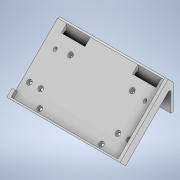
# Autodesk Inventor part: uMogi2_Tarto
Saved by Autodesk Inventor 2021 (Build 250183000, 183)
## iProperties
Created: 2021-04-12
Part Number: uMogi2_Tarto
Material: Generic
Document SubType Name: Modeling
Designer: Honti
Density: 1 g/cm^3
Appearance: Default
Author: Honti
Autodesk Inventor part; units mm, degrees
ref_plane "YZ Plane" through (0, 0, 0) normal (1, 0, 0) x (0, 1, 0)
ref_plane "XZ Plane" through (0, 0, 0) normal (0, 1, 0) x (-1, 0, 0)
ref_plane "XY Plane" through (0, 0, 0) normal (0, 0, 1) x (1, 0, 0)
sketch "Sketch1" plane through (0, 0, 0) normal (1, 0, 0) x (0, 1, 0)
  line L0 (0, 0) -> (33, 0)
  line L1 (-27.1041, 63.1041) -> (-29.2254, 60.9828)
  line L2 (28.7574, 3) -> (0, 3)
  line L3 (0, 3) -> (0, 0)
  line L4 (33, 0) -> (33, 3)
  line L5 (33, 3) -> (-27.1041, 63.1041)
  line L6 (28.7574, 3) -> (28.7574, 3)
  line L7 (28.7574, 3) -> (-29.2254, 60.9828)
  line L8 (15, 3) -> (15, 16.7574)
  dimension "d0" = 3
  dimension "d51" = 33
  dimension "d52" = 3
  dimension "d53" = 45
  dimension "d55" = 0
  dimension "d82" = 85
  dimension "d104" = 15
  constraints: 18 end point, 3 point on line, 3 vertical, 2 parallel, 2 perpendicular, 1 horizontal
  measures "d0" distance between parallel lines of L2 L0
  measures "d51" distance of L0.start L0.end
  measures "d52" distance between parallel lines of L5 L7
  measures "d53" angle of L2 L7
  measures "d55" distance of L2.start L6.end
  measures "d82" distance from line of L4.end L1
  measures "d104" distance between parallel lines of L3 L8
extrude "Extrusion1" add sketch "Sketch1" along normal mid plane 145 contours L3 L2 L7 L1 L5 L4 L0
sketch "Sketch2" plane through (-72.5, -23.5685, 59.5685) normal (0, 0.7071, 0.7071) x (1, 0, 0)
  line L0 (0, -5) -> (145, -5)
  line L1 (145, -5) -> (145, -3)
  line L2 (145, -3) -> (0, -3)
  line L3 (0, -3) -> (0, -5)
  line L4 (0, -3) -> (145, -3)
  line L5 (145, -3) -> (145, -1)
  line L6 (145, -1) -> (0, -1)
  line L7 (0, -1) -> (0, -3)
  line L8 (0, -5) -> (145, -5) projected
  line L9 (145, 82.1213) -> (143, 82.1213)
  line L10 (143, 82.1213) -> (143, -5)
  line L11 (143, -5) -> (145, -5)
  line L12 (145, -5) -> (145, 82.1213)
  line L13 (0, -5) -> (2, -5)
  line L14 (2, -5) -> (2, 4.5)
  line L15 (2, 4.5) -> (0, 4.5)
  line L16 (0, 4.5) -> (0, -5)
  line L17 (2, 4.5) -> (4, 4.5)
  line L18 (4, 4.5) -> (4, -5)
  line L19 (4, -5) -> (2, -5)
  line L20 (2, -5) -> (2, 4.5)
  line L21 (143, 82.1213) -> (141, 82.1213)
  line L22 (141, 82.1213) -> (141, -5)
  line L23 (141, -5) -> (143, -5)
  line L24 (143, -5) -> (143, 82.1213)
  line L25 (145, 80) -> (145, -5) projected
  line L26 (0, 80) -> (145, 80) projected
  line L27 (0, 82.1213) -> (145, 82.1213) projected
  point P0 (72.5, 58.7868)
  point P1 (2, -3)
  point P2 (143, -3)
  point P3 (141, -1)
  point P4 (4, -1)
  point P5 (141, -3)
  point P6 (4, -3)
  point P7 (145, -3)
  dimension "d7" = 2
  dimension "d8" = 2
  dimension "d9" = 2
  dimension "d10" = 2
  dimension "d11" = 2
  dimension "d12" = 2
  dimension "d20" = 7.5
  constraints: 48 end point, 12 parallel, 6 horizontal, 6 perpendicular, 5 collinear, 3 point on line
  measures "d7" distance of L2.end L0.start
  measures "d8" distance between parallel lines of L2 L6
  measures "d9" distance of L14.end L15.end
  measures "d10" distance of L9.start L9.end
  measures "d11" distance of L14.end L17.end
  measures "d12" distance of L9.end L21.end
  measures "d20" distance between parallel lines of L2 L17
extrude "Extrusion2" add sketch "Sketch2" along normal blind 7 contours L3 L2 L14 L0 | L14 L2 L18 L0 | L7 L6 L14 L2 | L18 L2 L22 L0 | L14 L6 L18 L2 | L16 L15 L14 L6 | L22 L2 L10 L0 | L14 L17 L18 L6 | L10 L2 L1 L0 | L22 L6 L10 L2 | L10 L6 L5 L2 | L22 L26 L10 L6 | L10 L26 L12 L6 | L22 L21 L10 L26 | L10 L9 L12 L26
extrude "Extrusion3" cut sketch "Sketch2" along normal blind 4 contours L14 L6 L18 L2 | L18 L6 L22 L2 | L14 L17 L18 L6 | L22 L6 L10 L2 | L22 L26 L10 L6 | L22 L21 L10 L26
chamfer "Chamfer1" distance 2 angle 45 2 edges at (-68.5, -20.2098, 61.8666) (68.5, 7.2335, 34.4234)
sketch "Sketch6" plane through (-72.5, 35.4142, 0.5858) normal (0, 0.7071, 0.7071) x (1, 0, 0)
  line L0 (33, -26.4142) -> (112, -26.4142) construction
  line L1 (112, -26.4142) -> (112, -82.4142) construction
  line L2 (112, -82.4142) -> (33, -82.4142) construction
  line L3 (33, -82.4142) -> (33, -26.4142) construction
  circle A0 centre (33, -26.4142) radius 1.75
  circle A1 centre (112, -26.4142) radius 1.75
  circle A2 centre (112, -82.4142) radius 1.75
  circle A3 centre (33, -82.4142) radius 1.75
  line L4 (0, -78.9142) -> (0, -3.4142) projected
  line L5 (2, -86.4142) -> (143, -86.4142) projected
  line L6 (72.5, -112.7506) -> (72.5, 22.6042) projected
  line L7 (-17.9809, -66.4142) -> (202.9102, -66.4142) construction
  circle A4 centre (8.5, -66.4142) radius 1.75
  circle A5 centre (23, -66.4142) radius 1.75
  circle A6 centre (122, -66.4142) radius 1.75
  circle A7 centre (136.5, -66.4142) radius 1.75
  line L8 (0, -6.4142) -> (145, -6.4142) projected
  circle A8 centre (33, -26.4142) radius 3
  circle A9 centre (112, -26.4142) radius 3
  circle A10 centre (8.5, -66.4142) radius 3
  circle A11 centre (23, -66.4142) radius 3
  circle A12 centre (122, -66.4142) radius 3
  circle A13 centre (136.5, -66.4142) radius 3
  circle A14 centre (33, -82.4142) radius 3
  circle A15 centre (112, -82.4142) radius 3
  line L9 (2, -66.4142) -> (28.3487, -66.4142)
  line L10 (28.3487, -66.4142) -> (28.3487, -37.4142)
  line L11 (28.3487, -37.4142) -> (2, -37.4142)
  line L12 (2, -37.4142) -> (2, -66.4142)
  point P0 (72.5, -24.6274)
  dimension "d39" = 3.5
  dimension "d40" = 3.5
  dimension "d41" = 3.5
  dimension "d42" = 3.5
  dimension "d43" = 56
  dimension "d44" = 79
  dimension "d58" = 4
  dimension "d59" = 3.5
  dimension "d60" = 3.5
  dimension "d61" = 3.5
  dimension "d62" = 3.5
  dimension "d63" = 14.5
  dimension "d64" = 14.5
  dimension "d67" = 60
  dimension "d69" = 10
  dimension "d70" = 10
  dimension "d71" = 6
  dimension "d73" = 6
  dimension "d74" = 6
  dimension "d75" = 6
  dimension "d76" = 6
  dimension "d77" = 6
  dimension "d78" = 6
  dimension "d79" = 6
  dimension "d105" = 29
  constraints: 18 end point, 16 centre point, 12 coincident, 5 point on line, 4 parallel, 3 horizontal, 2 perpendicular, 1 other
  measures "d39" diameter of A0
  measures "d40" diameter of A1
  measures "d41" diameter of A3
  measures "d42" diameter of A2
  measures "d43" distance of L2.end L0.start
  measures "d44" distance of L1.end L2.end
  measures "d58" distance between parallel lines of L2 L5
  measures "d59" diameter of A4
  measures "d60" diameter of A5
  measures "d61" diameter of A6
  measures "d62" diameter of A7
  measures "d63" distance of A5.centre A4.centre
  measures "d64" distance of A7.centre A6.centre
  measures "d67" distance between parallel lines of L8 L7
  measures "d69" distance from line of A5.centre L3
  measures "d70" distance from line of L1 A6.centre
  measures "d71" diameter of A8
  measures "d73" diameter of A9
  measures "d74" diameter of A12
  measures "d75" diameter of A13
  measures "d76" diameter of A11
  measures "d77" diameter of A10
  measures "d78" diameter of A15
  measures "d79" diameter of A14
  measures "d105" distance of L11.end L9.start
extrude "Extrusion6" cut sketch "Sketch6" against normal up to surface (3 mm away) contours A0 | A1 | A2 | A3 | L9 A4 | A4 L9 | L9 A5 | A5 L9 | A6 | A7
extrude "Extrusion7" cut sketch "Sketch6" against normal blind 2 contours L9 A10 A4 | A4 L9 A10 | L9 A5 A11 | A11 L9 A5 | A8 | A9 | A12 | A13 | A14 | A15
sketch "Sketch8" plane through (-72.5, 0, 0) normal (0, 1, 0) x (1, 0, 0)
  line L0 (103, -3) -> (133, -3)
  line L1 (133, -3) -> (133, -10)
  line L2 (133, -10) -> (103, -10)
  line L3 (103, -10) -> (103, -3)
  line L4 (0, -3) -> (145, -3) projected
  line L5 (133, -6.5) -> (103, -6.5)
  line L6 (143, -61.6899) -> (143, -3) projected
  line L7 (143, -61.6899) -> (143, -64.5183) projected
  line L8 (143, -64.5183) -> (143, -4.3284) projected
  line L9 (143, -1.5) -> (143, -4.3284) projected
  line L10 (143, -3) -> (143, -1.5) projected
  point P0 (72.5, 0)
  point P1 (136, -6.5)
  dimension "d88" = 7
  dimension "d89" = 30
  dimension "d111" = 10
  constraints: 10 end point, 3 parallel, 2 midpoint, 1 collinear, 1 horizontal, 1 perpendicular
  measures "d88" distance of L2.end L0.start
  measures "d89" distance of L1.end L2.end
  measures "d111" distance between parallel lines of L1 L8
extrude "Extrusion9" cut sketch "Sketch8" along normal blind 32 contours L5 L1 L2 L3
extrude "Extrusion10" cut sketch "Sketch8" along normal blind 35 contours L0 L1 L5 L3
mirror "Mirror2" about plane through (0, 0, 0) normal (1, 0, 0) of "Extrusion9", "Extrusion10"
fillet "Fillet1" radius 2 3 edges at (66.5, 28.7574, 3) (0, 28.7574, 3) (-66.5, 28.7574, 3)
sketch "Sketch9" plane through (-72.5, 0, 3) normal (0, 0, 1) x (1, 0, 0)
  circle A0 centre (15, 15) radius 2.25
  circle A1 centre (130, 15) radius 2.25
  line L0 (15, 15) -> (130, 15) construction
  line L1 (145, 0) -> (0, 0) projected
  line L2 (0, 33) -> (0, 0) projected
  line L3 (145, 0) -> (145, 33) projected
  circle A2 centre (15, 15) radius 1.75
  circle A3 centre (130, 15) radius 1.75
  point P0 (72.5, 0)
  dimension "d95" = 4.5
  dimension "d96" = 4.5
  dimension "d97" = 15
  dimension "d98" = 15
  dimension "d99" = 15
  dimension "d106" = 3.5
  dimension "d107" = 3.5
  constraints: 4 centre point, 2 coincident, 2 end point, 1 horizontal
  measures "d95" diameter of A0
  measures "d96" diameter of A1
  measures "d97" distance between parallel lines of L1 L0
  measures "d98" distance from line of L2 L0.start
  measures "d99" distance from line of L0.end L3
  measures "d106" diameter of A2
  measures "d107" diameter of A3
extrude "Extrusion11" cut sketch "Sketch9" against normal through all contours A0 | A1 | A2 | A3
sketch "Sketch10" plane through (72.5, 0, 0) normal (1, 0, 0) x (0, 0, -1)
  line L0 (-3, 33) -> (-1.5, 34.5) projected
  line L1 (-1.5, 34.5) -> (0, 33)
  line L2 (0, 33) -> (-3, 33)
  line L3 (-3, 33) -> (0, 33) projected
  line L4 (-1.5, 34.5) -> (-3, 33)
  point P0 (0, 0)
  constraints: 6 end point, 2 perpendicular, 1 point on line
extrude "Extrusion12" add sketch "Sketch10" against normal blind 2
extrude "Extrusion13" cut sketch "Sketch9" along normal through all contours A2 | A3
equation "\"d11\" = d8"
equation "\"d12\" = d11"
equation "\"d40\" = d39"
equation "\"d41\" = d39"
equation "\"d42\" = d39"
equation "\"d60\" = d59"
equation "\"d61\" = d60"
equation "\"d62\" = d59"
equation "\"d64\" = d63"
equation "\"d73\" = d71"
equation "\"d74\" = d73"
equation "\"d75\" = d73"
equation "\"d76\" = d71"
equation "\"d77\" = d71"
equation "\"d78\" = d75"
equation "\"d79\" = d76"
equation "\"d96\" = d95"
body "Solid1"
